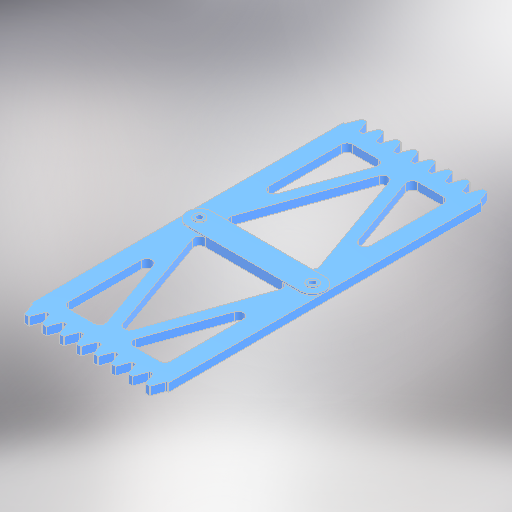
# Autodesk Inventor part: AP3.0_rack-timing
Saved by Autodesk Inventor 2025.3 (Build 293356030, 356C)
## iProperties
Created: 2026-06-07
Part Number: AP3.0_rack-timing
Material: 一般
Document SubType Name: Modeling
Designer: ibuki_ono
Density: 1 g/cm^3
Appearance: 滑らか - 黒
Author: ibuki_ono
## iProperties of the stored document AP3.0_rack-timing_3D プリント.ipt
Created: 2026-08-06
Part Number: AP3.0_rack-timing_3D プリント
Material: 一般
Document SubType Name: Modeling
Designer: ibuki_ono
Density: 1 g/cm^3
Appearance: 既定
Author: ibuki_ono
Autodesk Inventor part; units mm, degrees
ref_plane "YZ Plane" through (0, 0, 0) normal (1, 0, 0) x (0, 1, 0)
ref_plane "XZ Plane" through (0, 0, 0) normal (0, 1, 0) x (-1, 0, 0)
ref_plane "XY Plane" through (0, 0, 0) normal (0, 0, 1) x (1, 0, 0)
sketch "スケッチ1" plane through (0, 0, 0) normal (0, 1, 0) x (-1, 0, 0)
  line L0 (-25.1327, -61.5) -> (25.1327, -61.5)
  line L1 (25.1327, -61.5) -> (25.1327, 61.5)
  line L2 (25.1327, 61.5) -> (-25.1327, 61.5)
  line L3 (-25.1327, 61.5) -> (-25.1327, -61.5)
  line L4 (-25.1327, -61.5) -> (25.1327, 61.5) construction
  line L5 (25.1327, -61.5) -> (-25.1327, 61.5) construction
  point P0 (0, 0)
  dimension "d0" = 50.2655
  dimension "d1" = 123
  constraints: 12 end point, 2 midpoint, 2 parallel, 1 horizontal, 1 perpendicular
  measures "d0" distance of L1.end L2.end
  measures "d1" distance of L0.end L1.end
extrude "押し出し1" add sketch "スケッチ1" along normal blind 3
sketch "スケッチ2" plane through (0, 3, 0) normal (0, 1, 0) x (1, 0, 0)
  line L0 (-25.1327, -61.5) -> (25.1327, -61.5) projected
  line L1 (25.1327, -61.5) -> (25.1327, 61.5) projected
  line L2 (25.1327, -61.5) -> (18.8496, -61.5)
  line L3 (18.8496, -61.5) -> (18.8496, -57)
  line L4 (18.8496, -57) -> (25.1327, -57)
  line L5 (25.1327, -57) -> (25.1327, -61.5)
  line L6 (21.9911, -57) -> (21.9911, -61.5) construction
  line L7 (18.8496, -59.5) -> (25.1327, -59.5) construction
  line L8 (24.4719, -57) -> (22.834, -61.5)
  line L9 (24.4719, -57) -> (29.2607, -57) construction
  line L10 (21.1483, -61.5) -> (19.5104, -57)
  line L11 (21.1483, -61.5) -> (25.9371, -61.5) construction
  point P0 (0, 0)
  point P1 (20.4204, -59.5)
  point P2 (23.5619, -59.5)
  point P3 (25.1327, -57)
  dimension "d4" = 3.1416
  dimension "d5" = 2
  dimension "d6" = 2.5
  dimension "d7" = 110
  dimension "d8" = 110
  dimension "d9" = 1.5708
  dimension "d10" = 1.5708
  constraints: 20 end point, 10 point on line, 3 horizontal, 2 equal length, 2 midpoint, 2 parallel, 2 perpendicular
  measures "d4" distance between parallel lines of L1 L6
  measures "d5" distance between parallel lines of L0 L7
  measures "d6" distance between parallel lines of L4 L7
  measures "d7" angle of L8 L9
  measures "d8" angle of L11 L10
  measures "d9" distance from line of L1 point (23.562, -59.5)
  measures "d10" distance from line of L3 point (20.42, -59.5)
extrude "押し出し2" cut sketch "スケッチ2" against normal through all contours L3 L4 L10 L0 | L8 L4 L1 L0
fillet "フィレット1" radius 0.3 2 edges at (24.4719, 1.5, 57) (19.5104, 1.5, 57)
chamfer "面取り1" distance 0.1 angle 45 2 edges at (22.834, 1.5, 61.5) (21.1483, 1.5, 61.5)
pattern_linear "矩形状パターン1" count 8 spacing 6.2832 along (-1, 0, 0) of "押し出し2", "フィレット1", "面取り1"
mirror "ミラー1" about plane through (0, 0, 0) normal (0, 0, 1) of "押し出し2"
fillet "フィレット3" radius 0.3 2 edges at (19.5104, 1.5, -57) (24.4719, 1.5, -57)
chamfer "面取り2" distance 0.1 angle 45 2 edges at (22.834, 1.5, -61.5) (21.1483, 1.5, -61.5)
pattern_linear "矩形状パターン2" count 8 spacing 6.2832 along (-1, 0, 0) of "ミラー1", "面取り2", "フィレット3"
sketch "スケッチ4" plane through (0, 3, 0) normal (0, 1, 0) x (1, 0, 0)
  line L0 (20.6327, 0) -> (-20.6327, 0) construction
  line L1 (-25.1327, 61.5) -> (-25.1327, -57) projected
  line L2 (20.6327, 4.5) -> (-20.6327, 4.5)
  line L3 (-20.6327, -4.5) -> (20.6327, -4.5)
  arc A0 (20.6327, -4.5) -> (20.6327, 4.5) centre (20.6327, 0) ccw
  arc A1 (-20.6327, 4.5) -> (-20.6327, -4.5) centre (-20.6327, 0) ccw
  point P0 (0, 0)
  point P1 (-26.7035, -60.05)
  point P2 (-25.1327, -57.8)
  dimension "d26" = 9
  constraints: 8 end point, 4 point on circle, 4 tangent, 2 centre point, 1 horizontal, 1 midpoint, 1 parallel, 2 other
  measures "d26" diameter of A1
extrude "押し出し4" add sketch "スケッチ4" along normal blind 0.5
sketch "スケッチ5" plane through (0, 3.5, 0) normal (0, 1, 0) x (1, 0, 0)
  arc A0 (-20.6327, 4.5) -> (-20.6327, -4.5) centre (-20.6327, 0) ccw projected
  arc A1 (20.6327, -4.5) -> (20.6327, 4.5) centre (20.6327, 0) ccw projected
  circle A2 centre (-20.6327, 0) radius 2
  circle A3 centre (20.6327, 0) radius 2
  point P0 (0, 0)
  point P1 (23.7035, 3)
  point P2 (-23.7035, -3)
  dimension "d36" = 4
  dimension "d37" = 4
  constraints: 2 centre point, 2 coincident
  measures "d36" diameter of A2
  measures "d37" diameter of A3
extrude "押し出し5" add sketch "スケッチ5" along normal blind 0.4
sketch "スケッチ6" plane through (-20.6327, 3.9, 0) normal (0, 1, 0) x (1, 0, 0)
  circle A0 centre (0, 0) radius 2 projected
  circle A1 centre (41.2655, 0) radius 2 projected
  point P0 (20.6327, 0)
hole "穴1" at (20.6327, 3.9, 0) at (-20.6327, 3.9, 0) direction (0, -1, 0) diameter 2.2 end through all
sketch "スケッチ7" plane through (0, 0, 0) normal (0, -1, 0) x (1, 0, 0)
  circle A0 centre (20.6327, 0) radius 1.1 projected
  circle A1 centre (-20.6327, 0) radius 1.1 projected
  circle A2 centre (20.6327, 0) radius 2 projected
  line L0 (20.6327, 2.3671) -> (22.6827, 1.1836)
  line L1 (22.6827, 1.1836) -> (22.6827, -1.1836)
  line L2 (22.6827, -1.1836) -> (20.6327, -2.3671)
  line L3 (20.6327, -2.3671) -> (18.5827, -1.1836)
  line L4 (18.5827, -1.1836) -> (18.5827, 1.1836)
  line L5 (18.5827, 1.1836) -> (20.6327, 2.3671)
  line L6 (-20.6327, 2.3671) -> (-18.5827, 1.1836)
  line L7 (-18.5827, 1.1836) -> (-18.5827, -1.1836)
  line L8 (-18.5827, -1.1836) -> (-20.6327, -2.3671)
  line L9 (-20.6327, -2.3671) -> (-22.6827, -1.1836)
  line L10 (-22.6827, -1.1836) -> (-22.6827, 1.1836)
  line L11 (-22.6827, 1.1836) -> (-20.6327, 2.3671)
  point P0 (0, 0)
  dimension "d38" = 4.1
  dimension "d39" = 4.1
  constraints: 24 end point, 2 coincident, 2 vertical alignment, 26 other
  measures "d38" distance between parallel lines of L4 L1
  measures "d39" distance between parallel lines of L10 L7
extrude "押し出し6" cut sketch "スケッチ7" against normal blind 1.6 contours A0 | A2 | L0 L1 L2 L3 L4 L5 | L6 L7 L8 L9 L10 L11
sketch "スケッチ8" plane through (0, 3, 0) normal (0, 1, 0) x (1, 0, 0)
  circle A0 centre (-20.6327, 0) radius 2 projected
  circle A1 centre (20.6327, 0) radius 2 projected
  circle A2 centre (-20.6327, 0) radius 1.1 projected
  line L0 (-20.6327, 0) -> (0, -58) construction
  circle A3 centre (20.6327, 0) radius 1.1 projected
  line L1 (0, -58) -> (20.6327, 0) construction
  line L2 (0, -52.0327) -> (-16.9091, -4.5)
  line L3 (20.6327, -4.5) -> (-20.6327, -4.5) projected
  line L4 (16.9091, -4.5) -> (0, -52.0327)
  line L5 (-16.9091, -4.5) -> (15.4665, -4.5)
  line L6 (-20.6327, 0) -> (-20.6327, -58) construction
  line L7 (-25.1327, 0) -> (-25.1327, -57) construction
  line L8 (-20.6327, 0) -> (37.3673, 0) construction
  arc A4 (20.6327, -4.5) -> (25.1327, 0) centre (20.6327, 0) ccw construction
  line L9 (20.6327, 0) -> (20.6327, -58) construction
  line L10 (20.6327, 0) -> (78.6327, 0) construction
  line L11 (-4.3283, -51.8) -> (-18.6327, -11.5894)
  line L12 (-18.6327, -11.5894) -> (-18.6327, -51.8)
  line L13 (-18.6327, -51.8) -> (-4.3283, -51.8)
  line L14 (4.3283, -51.8) -> (18.6327, -51.8)
  line L15 (18.6327, -51.8) -> (18.6327, -11.5894)
  line L16 (18.6327, -11.5894) -> (4.3283, -51.8)
  line L17 (-20.6327, -4.5) -> (20.6327, -4.5) projected
  line L18 (-19.3004, -57.8) -> (-18.3987, -57.8) projected
  point P0 (0, 0)
  point P1 (-25.1327, -57.8)
  point P2 (-22.442, -57.8)
  point P3 (-21.5403, -57.8)
  point P4 (-19.3004, -57)
  point P5 (-18.3987, -57)
  dimension "d42" = 58
  dimension "d43" = 2
  dimension "d44" = 2
  dimension "d45" = 58
  dimension "d46" = 90
  dimension "d47" = 58
  dimension "d48" = 90
  dimension "d49" = 2
  dimension "d50" = 2
  dimension "d51" = 2
  dimension "d52" = 2
  dimension "d53" = 6
  constraints: 30 end point, 8 parallel, 5 point on line, 4 perpendicular, 2 horizontal, 2 vertical, 1 vertical alignment, 1 other
  measures "d42" distance of point (0, 0) L0.end
  measures "d43" distance between parallel lines of L2 L0
  measures "d44" distance between parallel lines of L1 L4
  measures "d45" distance of L0.start L6.end
  measures "d46" angle of L6 L8
  measures "d47" distance of L9.start L9.end
  measures "d48" angle of L9 L10
  measures "d49" distance between parallel lines of L0 L11
  measures "d50" distance between parallel lines of L16 L1
  measures "d51" distance between parallel lines of L9 L15
  measures "d52" distance between parallel lines of L6 L12
extrude "押し出し7" cut sketch "スケッチ8" against normal through all contours L2 L3 L4 | L13 L12 L11 | L16 L15 L14
fillet "フィレット4" radius 2 9 edges at (18.6327, 1.5, 11.5894) (18.6327, 1.5, 51.8) (4.3283, 1.5, 51.8) (0, 1.5, 52.0327) (-4.3283, 1.5, 51.8) (-18.6327, 1.5, 51.8) (16.9091, 1.5, 4.5) (-16.9091, 1.5, 4.5) (-18.6327, 1.5, 11.5894)
mirror "ミラー2" about plane through (0, 0, 0) normal (0, 0, 1) of "押し出し7", "フィレット4"
sketch "スケッチ9" plane through (0, 1.6, 0) normal (0, -1, 0) x (1, 0, 0)
  circle A0 centre (20.6327, 0) radius 1.1 projected
  line L0 (18.5827, -1.1836) -> (18.5827, 1.1836) projected
  line L1 (20.6327, -2.3671) -> (18.5827, -1.1836) projected
  line L2 (22.6827, -1.1836) -> (20.6327, -2.3671) projected
  line L3 (22.6827, 1.1836) -> (22.6827, -1.1836) projected
  line L4 (20.6327, 2.3671) -> (22.6827, 1.1836) projected
  line L5 (18.5827, 1.1836) -> (20.6327, 2.3671) projected
  line L6 (21.7327, 1.7321) -> (21.7327, -1.7321)
  line L7 (21.5827, -1.8187) -> (18.5827, -0.0866)
  line L8 (18.5827, 0.0866) -> (21.5827, 1.8187)
  line L9 (22.6827, 1.1836) -> (22.6827, -1.1836) projected
  line L10 (20.6327, -2.3671) -> (18.5827, -1.1836) projected
  line L11 (18.5827, 1.1836) -> (20.6327, 2.3671) projected
  circle A1 centre (20.6327, 0) radius 1.1 projected
  point P0 (0, 0)
  point P1 (20.0827, 0.9526)
  point P2 (20.0827, -0.9526)
  point P3 (21.7327, 0)
  constraints: 6 end point, 6 point on line, 3 parallel, 3 tangent, 1 vertical
extrude "押し出し8" cut sketch "スケッチ9" against normal blind 0.2 contours L6 L2 L7 A0 | A0 L8 L4 L6 | A0 L7 L0 L8
mirror "ミラー3" about plane through (0, 0, 0) normal (1, 0, 0) of "押し出し8"
equation "\"d4\" = 1.5708 * module"
equation "\"d5\" = module"
equation "\"d6\" = 1.25 * module"
equation "\"d9\" = 0.5 * d4"
equation "\"d10\" = d9"
equation "\"d19\" = 3.14159 * module"
equation "\"d63\" = 3.14159 * module"
equation "\"d37\" = d36"
equation "\"d44\" = d43"
equation "\"d50\" = d49"
equation "\"d51\" = d49"
equation "\"d52\" = d49"
equation "\"module\" = 2"
